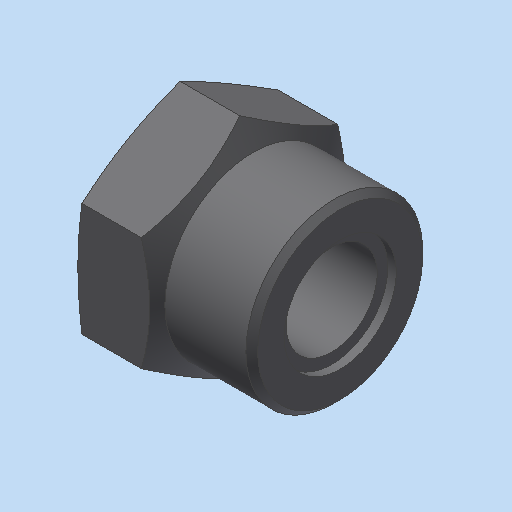
# Autodesk Inventor part: Sechskantmutter_ISO_7040___M4
Saved by Autodesk Inventor 2023.3 (Build 273359000, 359)
## iProperties
Shininess: 64.0
Length Units: 11269
Angle Units: 11279
Time Units: 11290
Mass Units: 11283
Length Display Precision: 3
Angle Display Precision: 2
Compacted: True
Part Number: Sechskantmutter_ISO_7040___M4
Document SubType Name: Modeling
Created: 2004-03-22
Material: xStahl_AnP_Dummymaterial
Description: =<RBPARTNOTITLE2>
Vendor: NORM8
Designer: S.Riedelsheimer
Manufacturer: Standard
Standards Organization: Custom
Mass: 1.25817 g
Surface Area: 2.53356 cm^2
Volume: 0.160276 cm^3
Density: 7.85 g/cm^3
Appearance: Stahl - normal AnP
Density: 0.0
Volumn: 0.0
Area: 0.0
PropertySet Name: Model Information
Control State: 0
Master: False
Checked Out: False
CNS_NB: Sechskantmutter ISO 7040 - M4
CNS_NN: ISO 7040
CNS_NT: Sechskantmutter  mit Klemmteil (mit nichtmetallischem Einsatz) Typ1
CNS_NBSYN: Sechskantmutter ISO 7040 - $NENN.
CNS_LINA: Sechskantmutter ISO 7040 - M4
CNS_NENN: M4
CNS_D: 4.000
CNS_D1: 3.240
CNS_P: 0.700
CNS_DA: 4.600
CNS_DW: 5.880
CNS_E: 7.660
CNS_M: 6.000
CNS_MG: 2.900
CNS_M1: 2.320
CNS_S: 7.000
CNS_KT: DUMMY
PSOL_IDENT_0: {C:\partsolutions8\data\23d-libs\bosch_bamberg\muttern\muttern_mit_klemmteil\din_en_iso_7040.prj},16
PSOL_IDENT_1: 5 {M=Nenngewinde},{VTYP=3D},{NB=Sechskantmutter ISO 7040 - M4},{NN=ISO 7040},{DATE=26.11.2003},{GEOM
PSOL_IDENT_2: DATE=26.11.2003},{VERSION=v2},{LINEID=20},{LINESUBID=-1},{WBVAR=}  {NB=Sechskantmutter ISO 7040 - M4
PSOL_IDENT_3: },{LINA=Sechskantmutter ISO 7040 - M4},{KT=DUMMY},{IDNR=},{NENN=M4},{D=4.000},{D1=3.240},{P=0.700},{
PSOL_IDENT_4: DA=4.600},{DW=5.880},{E=7.660},{M=6.000},{MG=2.900},{M1=2.320},{S=7.000}
RBPARTNOTITLE2: Sechskantmuttern mit Klemmteil (mit nichtmetallischem Einsatz)
RBPARTNOTITLE1: Prevailing torque type hexagon regular nuts (with non-metallic insert)
RBDRAWINGMISSINGSPEC: --
AnP_Kategorie: 4
RBPARTMADEOF: ISO 7040 - M4 - verzinkt
Title: Sechskantmutter ISO 7040 - M4
Author: S.Riedelsheimer
Keywords: =<RBPARTMADEOF>
Comments: =<RBSURFACE2>
Revision Number: 01
Autodesk Inventor part; units mm, degrees
sketch "Sketch_1" plane through (0, 0, 0) normal (0, 0, 1) x (1, 0, 0)
  line L0 (0, 0) -> (6, 0)
  line L1 (0, -2.94) -> (0.3411, -4.213)
  line L2 (0.3411, -4.213) -> (2.32, -4.213)
  line L3 (2.32, -4.213) -> (2.9, -3.15)
  line L4 (2.9, -3.15) -> (5.79, -3.15)
  line L5 (5.79, -3.15) -> (6, -2.94)
  line L6 (6, -2.94) -> (6, -2)
  line L7 (6, -2) -> (5.7, -2)
  line L8 (5.7, -2) -> (5.7, -1.62)
  line L9 (5.7, -1.62) -> (3.3, -1.62)
  line L10 (3.3, -1.62) -> (3.3, -2)
  line L11 (3.3, -2) -> (3, -2)
  line L12 (3, -2) -> (2.62, -1.62)
  line L13 (2.62, -1.62) -> (0.68, -1.62)
  line L14 (0.68, -1.62) -> (0, -2.3)
  line L15 (0, -2.3) -> (0, -2.94)
  constraints: 32 end point
revolve "Drehung1" add sketch "Sketch_1" angle 360 about axis through (0, 0, 0) along (1, 0, 0)
thread "Gewinde1" size "M4x0.7" class "6H" standard "ANSI Metric M Profile" length 2.7
sketch "Sketch_2" plane through (0, 0, 0) normal (-1, 0, 0) x (0, 0, 1)
  line L0 (7, 7) -> (-7, 7)
  line L1 (-7, 7) -> (-7, -7)
  line L2 (-7, -7) -> (7, -7)
  line L3 (7, -7) -> (7, 7)
  line L4 (2.0207, 3.5) -> (-2.0207, 3.5)
  line L5 (-2.0207, 3.5) -> (-4.0415, 0)
  line L6 (-4.0415, 0) -> (-2.0207, -3.5)
  line L7 (-2.0207, -3.5) -> (2.0207, -3.5)
  line L8 (2.0207, -3.5) -> (4.0415, 0)
  line L9 (4.0415, 0) -> (2.0207, 3.5)
  constraints: 20 end point
extrude "Extrusion1" cut sketch "Sketch_2" against normal blind 6.6
ref_plane "IP1_XY" through (0, 0, 0) normal (1, 0, 0) x (0, 0, -1)
ref_plane "IP1_YZ" through (0, 0, 0) normal (0, 0, -1) x (0, 1, 0)
ref_plane "IP2_XY" through (6, 0, 0) normal (1, 0, 0) x (0, 0, -1)
ref_plane "IP2_YZ" through (6, 0, 0) normal (0, 0, -1) x (0, 1, 0)
